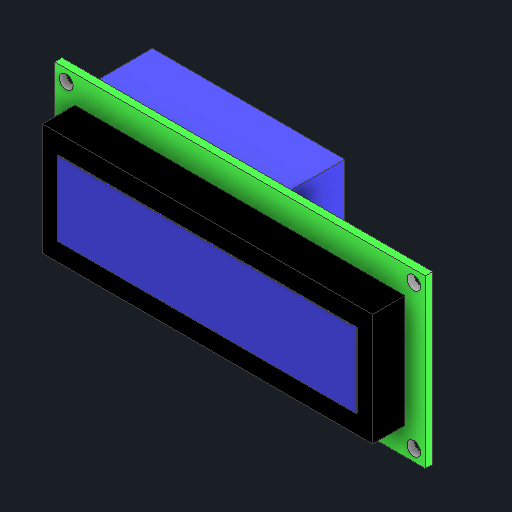
# Autodesk Inventor part: LCD 1602 I2C
Saved by Autodesk Inventor 2027.2 (Build 312334000, 334)
## iProperties
Created: 2026-11-06
Part Number: LCD 1602 I2C
Material: Generic
Description: 1602 character LCD with PCF8574 I2C backpack, typical dimensions (verify)
Document SubType Name: Modeling
Designer: isaac
Density: 1 g/cm^3
Appearance: Default
Author: isaac
Autodesk Inventor part; units mm, degrees
sketch "Sketch1" plane through (0, 0, 0) normal (0, 0, 1) x (1, 0, 0)
  line L0 (0, 0) -> (80, 0)
  line L1 (80, 0) -> (80, 36)
  line L2 (80, 36) -> (0, 36)
  line L3 (0, 36) -> (0, 0)
  constraints: 8 end point, 2 parallel, 1 horizontal, 1 perpendicular
extrude "PCB" add sketch "Sketch1" along normal blind 1.6
ref_plane "Work Plane1" through (0, 0, 1.6) normal (0, 0, 1) x (1, 0, 0)
sketch "Sketch2" plane through (0, 0, 1.6) normal (0, 0, 1) x (1, 0, 0)
  line L0 (4.4, 5.9) -> (75.6, 5.9)
  line L1 (75.6, 5.9) -> (75.6, 30.1)
  line L2 (75.6, 30.1) -> (4.4, 30.1)
  line L3 (4.4, 30.1) -> (4.4, 5.9)
  constraints: 8 end point, 2 parallel, 1 horizontal, 1 perpendicular
extrude "Bezel" add sketch "Sketch2" along normal blind 7
ref_plane "Work Plane2" through (0, 0, 8.6) normal (0, 0, 1) x (1, 0, 0)
sketch "Sketch3" plane through (0, 0, 8.6) normal (0, 0, 1) x (1, 0, 0)
  line L0 (7.75, 10) -> (72.25, 10)
  line L1 (72.25, 10) -> (72.25, 26)
  line L2 (72.25, 26) -> (7.75, 26)
  line L3 (7.75, 26) -> (7.75, 10)
  constraints: 8 end point, 2 parallel, 1 horizontal, 1 perpendicular
extrude "Screen" add sketch "Sketch3" along normal blind 0.2
sketch "Sketch4" plane through (0, 0, 0) normal (0, 0, 1) x (1, 0, 0)
  line L0 (7, 16) -> (48.5, 16)
  line L1 (48.5, 16) -> (48.5, 35)
  line L2 (48.5, 35) -> (7, 35)
  line L3 (7, 35) -> (7, 16)
  constraints: 8 end point, 2 parallel, 1 horizontal, 1 perpendicular
extrude "I2C backpack" add sketch "Sketch4" against normal blind 12.5
ref_plane "Work Plane3" through (0, 0, -2.5) normal (0, 0, 1) x (1, 0, 0)
sketch "Sketch5" plane through (0, 0, -2.5) normal (0, 0, 1) x (1, 0, 0)
  line L0 (1, 20.5) -> (7, 20.5)
  line L1 (7, 20.5) -> (7, 30.7)
  line L2 (7, 30.7) -> (1, 30.7)
  line L3 (1, 30.7) -> (1, 20.5)
  constraints: 8 end point, 2 parallel, 1 horizontal, 1 perpendicular
extrude "I2C 4-pin header" add sketch "Sketch5" against normal blind 2.5
sketch "Sketch6" plane through (0, 0, 0) normal (0, 0, 1) x (1, 0, 0)
  circle A0 centre (2.5, 2.5) radius 1.5
  circle A1 centre (77.5, 2.5) radius 1.5
  circle A2 centre (2.5, 33.5) radius 1.5
  circle A3 centre (77.5, 33.5) radius 1.5
  constraints: 4 centre point
extrude "M3 mounting holes" cut sketch "Sketch6" along normal through all both and the other way through all
body "Solid1"
